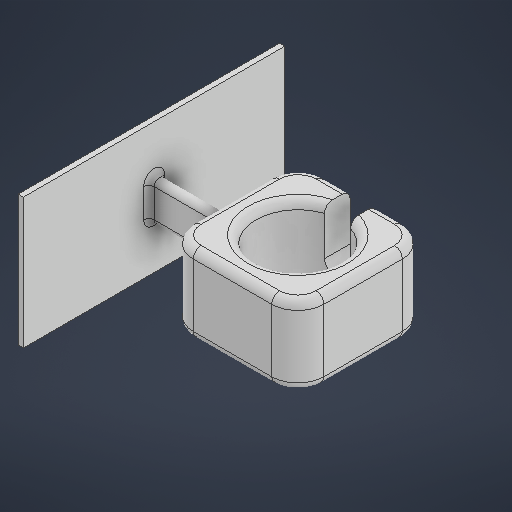
# Autodesk Inventor part: AntennaHolder
Saved by Autodesk Inventor 2027.1 (Build 311270010, 270A)
## iProperties
Created: 2026-10-08
Part Number: AntennaHolder
Material: Generic
Document SubType Name: Sheet Metal
Designer: pravo
Density: 1 g/cm^3
Sheet Metal Rule: Default_mm
Appearance: Default
Author: pravo
Autodesk Inventor part; units mm, degrees
ref_plane "YZ Plane" through (0, 0, 0) normal (1, 0, 0) x (0, 1, 0)
ref_plane "XZ Plane" through (0, 0, 0) normal (0, 1, 0) x (-1, 0, 0)
ref_plane "XY Plane" through (0, 0, 0) normal (0, 0, 1) x (1, 0, 0)
sketch "Sketch1" plane through (0, 0, 0) normal (1, 0, 0) x (0, 1, 0)
  line L0 (25, 50) -> (-25, 50)
  line L1 (-25, 50) -> (-25, -50)
  line L2 (-25, -50) -> (25, -50)
  line L3 (25, -50) -> (25, 50)
  line L4 (25, 50) -> (-25, -50) construction
  line L5 (-25, 50) -> (25, -50) construction
  point P0 (0, 0)
  dimension "d0" = 50
  dimension "d1" = 100
  constraints: 12 end point, 2 midpoint, 2 parallel, 1 horizontal, 1 perpendicular
  measures "d0" distance of L2.end L1.end
  measures "d1" distance of L1.end L0.end
extrude "Extrusion1" add sketch "Sketch1" along normal blind 2
sketch "Sketch2" plane through (2, 0, 0) normal (1, 0, 0) x (0, 0, -1)
  line L0 (-2, 7.5) -> (2, 7.5)
  line L1 (2, 7.5) -> (2, -7.5)
  line L2 (2, -7.5) -> (-2, -7.5)
  line L3 (-2, -7.5) -> (-2, 7.5)
  line L4 (-2, 7.5) -> (2, -7.5) construction
  line L5 (2, 7.5) -> (-2, -7.5) construction
  point P0 (0, 0)
  dimension "d4" = 4
  dimension "d5" = 15
  constraints: 12 end point, 2 midpoint, 2 parallel, 1 horizontal, 1 perpendicular
  measures "d4" distance of L1.end L2.end
  measures "d5" distance of L0.end L1.end
extrude "Extrusion2" add sketch "Sketch2" along normal blind 30
sketch "Sketch3" plane through (32, 0, 0) normal (1, 0, 0) x (0, 0, -1)
  line L0 (-25, 15) -> (25, 15)
  line L1 (25, 15) -> (25, -15)
  line L2 (25, -15) -> (-25, -15)
  line L3 (-25, -15) -> (-25, 15)
  line L4 (-25, 15) -> (25, -15) construction
  line L5 (25, 15) -> (-25, -15) construction
  point P0 (0, 0)
  dimension "d8" = 50
  dimension "d9" = 30
  constraints: 12 end point, 2 midpoint, 2 parallel, 1 horizontal, 1 perpendicular
  measures "d8" distance of L1.end L2.end
  measures "d9" distance of L0.end L1.end
extrude "Extrusion3" add sketch "Sketch3" along normal blind 50
sketch "Sketch4" plane through (32, 15, 25) normal (0, 1, 0) x (1, 0, 0)
  circle A0 centre (25, 25) radius 16
  line L0 (0, 0) -> (50, 0) projected
  line L1 (0, 50) -> (50, 50) projected
  line L2 (50, 50) -> (50, 0) projected
  point P0 (-32, 25)
  dimension "d12" = 25
  dimension "d13" = 50
  dimension "d14" = 50
  dimension "d15" = 25
  dimension "d16" = 32
  constraints: 1 centre point
  measures "d12" distance from line of L0 A0.centre
  measures "d13" distance of L0.start L0.end
  measures "d14" distance between parallel lines of L1 L0
  measures "d15" distance from line of L2 A0.centre
  measures "d16" diameter of A0
extrude "Extrusion4" cut sketch "Sketch4" against normal blind 25
sketch "Sketch5" plane through (32, -15, -25) normal (0, 0, -1) x (-1, 0, 0)
  line L0 (-41, 5) -> (-9, 5) projected
  line L1 (-41, 30) -> (-9, 30) projected
  circle A0 centre (-25, 12) radius 5
  line L2 (0, 30) -> (-50, 30) projected
  point P0 (32, 15)
  point P1 (-25, 30)
  dimension "d19" = 10
  dimension "d20" = 7
  dimension "d21" = 0
  constraints: 1 centre point, 1 midpoint
  measures "d19" diameter of A0
  measures "d20" distance from line of L0 A0.centre
  measures "d21" horizontal distance of A0.centre point (-25, 30)
extrude "Extrusion5" cut sketch "Sketch5" against normal up to surface
fillet "Fillet1" radius 10 4 edges at (82, 0, -25) (32, 0, 25) (32, 0, -25) (82, 0, 25)
fillet "Fillet2" radius 2 4 edges at (17, 7.5, -2) (17, -7.5, -2) (17, 7.5, 2) (17, -7.5, 2)
fillet "Fillet3" radius 2 4 edges at (32, 6.9144, -1.4144) (32, 0, 2) (32, -6.9144, -1.4144) (32, 0, -2)
fillet "Fillet4" radius 2 4 edges at (2, -6.9144, -1.4144) (2, 0, 2) (2, 6.9144, -1.4144) (2, 0, -2)
fillet "Fillet5" radius 3 17 edges at (41, 15, 0) (79.0711, 15, -22.0711) (82, 15, 0) (79.0711, 15, 22.0711) (57, 15, 25) (34.9289, 15, 22.0711) (32, 15, 0) (34.9289, 15, -22.0711) (57, 15, -25) (79.0711, -15, -22.0711) (82, -15, 0) (79.0711, -15, 22.0711) (57, -15, 25) (34.9289, -15, 22.0711) (32, -15, 0) (34.9289, -15, -22.0711) (57, -15, -25)
sketch "Sketch6" plane through (42, 15, -22) normal (0, 1, 0) x (1, 0, 0)
  line L0 (10, 3) -> (20, 3) projected
  line L1 (10, 3) -> (10, -6.8013)
  line L2 (10, -6.8013) -> (20, -6.8013)
  line L3 (20, -6.8013) -> (20, 3)
  line L4 (10, 3) -> (20, 3)
  point P0 (-42, -22)
  constraints: 8 end point, 2 perpendicular, 1 collinear, 1 vertical
extrude "Extrusion6" cut sketch "Sketch6" against normal up to surface
equation "\"d12\" = 0.5 * d14"
equation "\"d15\" = 0.5 * d13"
equation "\"BendRadius\" = Thickness"
equation "\"BendReliefWidth\" = Thickness"
equation "\"BendReliefDepth\" = 0.5 * Thickness"
equation "\"CornerReliefSize\" = 4 * Thickness"
equation "\"MinimumRemnant\" = 2 * Thickness"
equation "\"TransitionRadius\" = BendRadius"
equation "\"JacobiRadiusSize\" = BendRadius"
equation "\"GapSize\" = Thickness"
equation "\"Thickness\" = 0.5"
body "Solid1"
